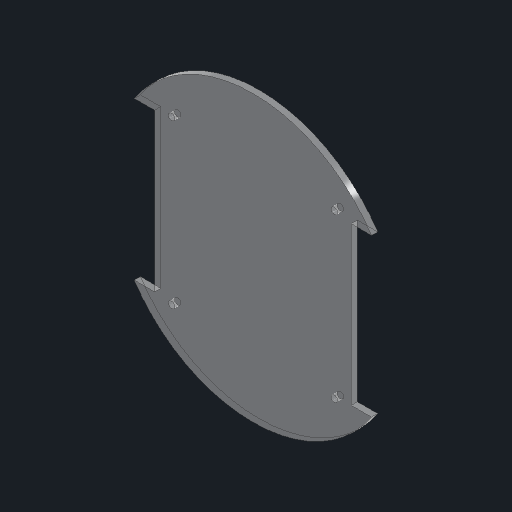
# Autodesk Inventor part: Chasis_Placa_2
Saved by Autodesk Inventor 2026.2 (Build 302298010, 298A)
## iProperties
Created: 2026-10-27
Part Number: Chasis_Placa_2
Material: Policarbonato, claro
Document SubType Name: Modeling
Designer: efrey
Density: 1.2 g/cm^3
Appearance: Policarbonato - Claro
Author: efrey
Autodesk Inventor part; units mm, degrees
ref_plane "YZ Plane" through (0, 0, 0) normal (1, 0, 0) x (0, 1, 0)
ref_plane "XZ Plane" through (0, 0, 0) normal (0, 1, 0) x (-1, 0, 0)
ref_plane "XY Plane" through (0, 0, 0) normal (0, 0, 1) x (1, 0, 0)
sketch "Boceto1" plane through (0, 0, 0) normal (0, 0, 1) x (1, 0, 0)
  line L0 (48.3293, 38.7) -> (48.3293, -38.7)
  line L1 (-48.3293, 38.7) -> (-48.3293, -38.7)
  circle A0 centre (40, -40) radius 1.6
  circle A1 centre (-40, -40) radius 1.6
  circle A2 centre (40, 40) radius 1.6
  circle A3 centre (-40, 40) radius 1.6
  line L2 (48.3293, 38.7) -> (58.3293, 38.7)
  line L3 (58.3293, -38.7) -> (48.3293, -38.7)
  line L4 (-58.3293, 38.7) -> (-48.3293, 38.7)
  line L5 (-48.3293, -38.7) -> (-58.3293, -38.7)
  arc A4 (58.3293, 38.7) -> (-58.3293, 38.7) centre (0, 0) ccw
  arc A5 (-58.3293, -38.7) -> (58.3293, -38.7) centre (0, 0) ccw
  dimension "d4" = 3.2
  dimension "d6" = 40
  dimension "d7" = 40
  dimension "d8" = 3.2
  dimension "d9" = 3.2
  dimension "d10" = 3.2
  dimension "d11" = 40
  dimension "d12" = 40
  dimension "d13" = 40
  dimension "d14" = 40
  dimension "d15" = 40
  dimension "d16" = 40
  dimension "d19" = 10
  dimension "d20" = 10
  dimension "d21" = 77.4
  dimension "d22" = 77.4
  dimension "d23" = 10
  dimension "d24" = 10
  dimension "d25" = 70
  dimension "d26" = 70
  constraints: 12 end point, 6 centre point, 4 parallel, 4 point on circle, 2 horizontal, 2 vertical, 1 coincident
  measures "d4" diameter of A0
  measures "d6" horizontal distance of A4.centre A0.centre
  measures "d7" horizontal distance of A4.centre A0.centre
  measures "d8" diameter of A1
  measures "d9" diameter of A2
  measures "d10" diameter of A3
  measures "d11" horizontal distance of A4.centre A2.centre
  measures "d12" horizontal distance of A4.centre A2.centre
  measures "d13" horizontal distance of A4.centre A3.centre
  measures "d14" horizontal distance of A4.centre A3.centre
  measures "d15" horizontal distance of A4.centre A1.centre
  measures "d16" horizontal distance of A4.centre A1.centre
  measures "d19" distance of L1.end L5.end
  measures "d20" distance of L4.start L1.start
  measures "d21" distance of L1.start L1.end
  measures "d22" distance of L0.start L0.end
  measures "d23" distance of L0.start L2.end
  measures "d24" distance of L3.start L0.end
  measures "d25" radius of A5
  measures "d26" radius of A4
extrude "Extrusión1" add sketch "Boceto1" along normal mid plane 3
